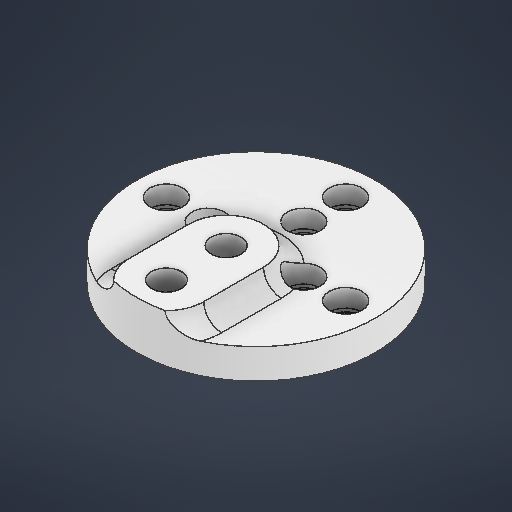
# Autodesk Inventor part: R-2
Saved by Autodesk Inventor 2026.2 (Build 302298010, 298A)
## iProperties
Created: 2026-03-20
Part Number: R-2
Material: ABS 플라스틱
Document SubType Name: Modeling
Designer: work
Density: 1.06 g/cm^3
Appearance: 매끄러움 - 흰색
Author: work
Autodesk Inventor part; units mm, degrees
ref_plane "YZ Plane" through (0, 0, 0) normal (1, 0, 0) x (0, 1, 0)
ref_plane "XZ Plane" through (0, 0, 0) normal (0, 1, 0) x (-1, 0, 0)
ref_plane "XY Plane" through (0, 0, 0) normal (0, 0, 1) x (1, 0, 0)
sketch "스케치1" plane through (0, 0, 0) normal (0, 1, 0) x (-1, 0, 0)
  circle A0 centre (0, -8) radius 2
  circle A1 centre (0, -15) radius 2
  line L0 (0, 0) -> (0, -15) construction
  circle A2 centre (0, 0) radius 20
  circle A3 centre (8, 0) radius 2
  circle A4 centre (15, 0) radius 2
  circle A5 centre (0, 8) radius 2
  circle A6 centre (0, 15) radius 2
  circle A7 centre (-8, 0) radius 2
  circle A8 centre (-15, 0) radius 2
  dimension "d0" = 4
  dimension "d1" = 4
  dimension "d2" = 7
  dimension "d3" = 8
  dimension "d4" = 40
  dimension "d7" = 360
  constraints: 9 centre point, 2 end point, 1 coincident, 1 point on line, 1 vertical, 17 other
  measures "d0" diameter of A0
  measures "d1" diameter of A1
  measures "d2" distance of L0.end A0.centre
  measures "d3" distance of L0.start A0.centre
  measures "d4" diameter of A2
extrude "돌출1" add sketch "스케치1" along normal blind 5 contours A2 | A5 | A6
sketch "스케치2" plane through (0, 5, 0) normal (0, 1, 0) x (1, 0, 0)
  circle A0 centre (0, 0) radius 20 projected
  circle A1 centre (15, 0) radius 2 projected
  circle A2 centre (8, 0) radius 2 projected
  circle A3 centre (-15, 0) radius 2 projected
  circle A4 centre (-8, 0) radius 2 projected
  circle A5 centre (0, 15) radius 2 projected
  circle A6 centre (0, 8) radius 2 projected
  circle A7 centre (-8, 0) radius 2.75
  circle A8 centre (0, 8) radius 2.75
  circle A9 centre (0, 15) radius 2.75
  circle A10 centre (8, 0) radius 2.75
  circle A11 centre (15, 0) radius 2.75
  circle A12 centre (-15, 0) radius 2.75
  dimension "d11" = 5.5
  dimension "d12" = 5.5
  dimension "d13" = 5.5
  dimension "d14" = 5.5
  dimension "d15" = 5.5
  dimension "d16" = 5.5
  constraints: 6 centre point, 6 coincident
  measures "d11" diameter of A7
  measures "d12" diameter of A8
  measures "d13" diameter of A9
  measures "d14" diameter of A10
  measures "d15" diameter of A11
  measures "d16" diameter of A12
extrude "돌출2" cut sketch "스케치2" against normal blind 3 contours A1 | A2 | A3 | A5 | A6 | A7 | A8 | A9 | A10 | A11 | A12
sketch "스케치3" plane through (0, 5, 0) normal (0, 1, 0) x (1, 0, 0)
  line L0 (0, -5) -> (0, -15) construction
  line L1 (-6.25, -5) -> (-6.25, -15)
  line L2 (6.25, -15) -> (6.25, -5)
  arc A0 (6.25, -5) -> (-6.25, -5) centre (0, -5) ccw
  arc A1 (-6.25, -15) -> (6.25, -15) centre (0, -15) ccw
  circle A2 centre (0, -15) radius 2.5
  circle A3 centre (0, -5) radius 2.5
  line L3 (0, 0) -> (0, -5) construction
  circle A4 centre (0, 8) radius 2.75 projected
  circle A5 centre (15, 0) radius 2.75 projected
  circle A6 centre (-8, 0) radius 2.75 projected
  circle A7 centre (0, 15) radius 2.75 projected
  circle A8 centre (8, 0) radius 2.75 projected
  circle A9 centre (-15, 0) radius 2.75 projected
  circle A10 centre (0, 0) radius 20 projected
  point P0 (0, -10)
  point P1 (-4.3047, -19.5313)
  point P2 (4.3047, -19.5313)
  dimension "d19" = 12.5
  dimension "d20" = 5
  dimension "d21" = 5
  dimension "d22" = 10
  dimension "d23" = 5
  constraints: 10 end point, 4 centre point, 4 point on circle, 4 tangent, 2 coincident, 2 vertical, 1 midpoint, 1 parallel
  measures "d19" diameter of A1
  measures "d20" diameter of A2
  measures "d21" diameter of A3
  measures "d22" distance of L0.start L0.end
  measures "d23" distance of L0.start L3.start
extrude "돌출3" add sketch "스케치3" along normal blind 3 contours A0 L2 A1 A10 L1 picked at (4.7904, -11.1141)
fillet "모깎기1" radius 3 5 edges at (5.7431, 5, 17.4656) (0, 5, -1.25) (-6.25, 5, 10) (-5.7431, 5, 17.4656) (6.25, 5, 10)
sketch "스케치4" plane through (0, 5, 5) normal (0, 1, 0) x (1, 0, 0)
  circle A0 centre (0, 0) radius 2.5 projected
  circle A1 centre (0, -10) radius 2.5 projected
  point P0 (0, 5)
extrude "돌출4" cut sketch "스케치4" against normal through all
sketch "스케치5" plane through (0, 0, 0) normal (0, -1, 0) x (1, 0, 0)
  circle A0 centre (0, 5) radius 2.5 projected
  circle A1 centre (0, 15) radius 2.5 projected
  circle A2 centre (0, 0) radius 20 projected
  circle A3 centre (15, 0) radius 2 projected
  circle A4 centre (8, 0) radius 2 projected
  circle A5 centre (-15, 0) radius 2 projected
  circle A6 centre (-8, 0) radius 2 projected
  circle A7 centre (0, -15) radius 2 projected
  circle A8 centre (0, -8) radius 2 projected
  circle A9 centre (0, 5) radius 3.5
  circle A10 centre (0, 15) radius 3.5
  dimension "d29" = 7
  dimension "d30" = 7
  constraints: 2 centre point, 2 coincident
  measures "d29" diameter of A9
  measures "d30" diameter of A10
extrude "돌출5" cut sketch "스케치5" against normal blind 4 contours A0 | A1 | A9 | A10
